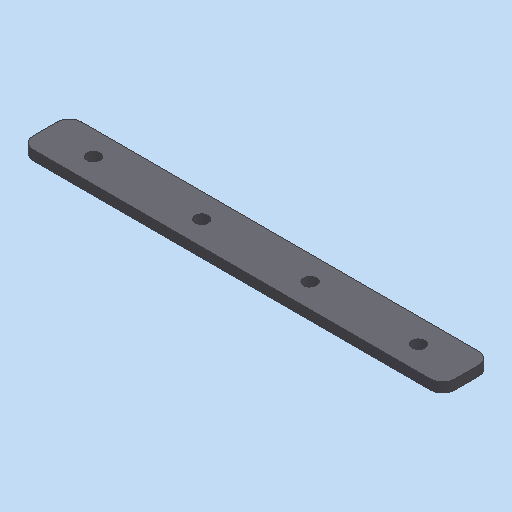
# Autodesk Inventor part: MM0861AN200_G22_145
Saved by Autodesk Inventor 2023.3 (Build 273359000, 359)
## iProperties
Part Number: MM0861AN200_G22_145
Material: 3.1645 AlCu4PbMgMn - AW 2007
Description: =<RBPARTNOTITLE2>
Document SubType Name: Blech
Designer: Benutzer
Mass: 38.572 g
Surface Area: 85.6914 cm^2
Volume: 13.534 cm^3
Density: 2.85 g/cm^3
Sheet Metal Rule: Standard_mm
Appearance: grau AnP
Vendor: ASW
RBCHANGEDESCRIPTION1: Erstfreigabe
RBCHANGENO1: 00
RBDOCUMENTTYPE: DRF
RBDOCUMENTVERSION: 00
RBDRAWINGMAINSCALE: 1:1
RBDRAWINGMISSINGSPEC: --
RBDRAWINGVOLUME: --
RBDSV1: 0850
RBGBDETAILS: 43274
RBGBEDGESIN1: +0,5
RBGBEDGESIN2: +0,2
RBGBEDGESOUT1: -0,3
RBGBEDGESOUT2: -0,1
RBMATERIAL: =<Material>
RBMATMEETS: --
RBMATNO: =<Part Number>
RBORGUNITRESPONSIBLE1: AnP/TEF1
RBPARTMADEOF: 4 x 20 x 175 (FM)
RBPARTNO: SIEHE MNR
RBPARTNOTITLE1: manufactured part
RBPARTNOTITLE2: Anfertigungsteil
RBPARTSAFETYINDICATOR: --
RBSURFACE: anodised grey
RBSURFACE2: eloxiert grau
RBZEDGESNORM: ISO13715:2002-06
RBZGENDIMCLASS: m
RBZGENDIMNORM: ISO 2768-1:1989-11
RBZGENGEOCLASS: H
RBZGENGEONORM: ISO 2768-2:1989-11
RBZSURFACENORM: ISO13D2:2002-02
RBZTOLERANCENORM: ISO 14405-1:2010-12
AnP_Material: =<Material>
AnP_TemplVers: 20190222
AnP_Kategorie: 1
MaxAbmaße: 4 x 20 x 175 (FM)
Author: Benutzer
Keywords: =<RBPARTMADEOF>
Comments: =<RBSURFACE2>
Revision Number: 01
Autodesk Inventor part; units mm, degrees
ref_plane "XZ Plane" through (0, 0, 0) normal (0, 1, 0) x (-1, 0, 0)
sketch "Skizze1" plane through (0, 0, 0) normal (0, 0, 1) x (1, 0, 0)
  line L0 (0, 0) -> (75, 0)
  line L1 (75, 0) -> (75, 20)
  line L2 (75, 20) -> (0, 20)
  line L3 (0, 20) -> (0, 0)
  dimension "d0" = 75
  dimension "d1" = 20
  measures "d0" distance of L2.end L1.end
  measures "d1" distance of L1.end L0.end
extrude "Grobblech1" add sketch "Skizze1" along normal blind 4
sketch "Skizze2" plane through (0, 0, 4) normal (0, 0, 1) x (1, 0, 0)
  line L0 (0, 20) -> (75, 20) projected
  line L1 (0, 0) -> (0, 20) projected
  point P0 (15, 10)
  point P1 (60, 10)
  dimension "d3" = 10
  dimension "d4" = 45
  dimension "d5" = 15
  constraints: 1 horizontal alignment
  measures "d3" distance from line of point (15, 10) L0
  measures "d4" distance of point (60, 10) point (15, 10)
  measures "d5" distance from line of point (15, 10) L1
hole "Bohrung1" at (15, 10, 4) at (60, 10, 4) direction (0, 0, -1) diameter 5.5 depth 4 tip angle 118
sketch "Skizze3" plane through (75, 0, 0) normal (1, 0, 0) x (0, 0, -1)
  line L0 (-4, 20) -> (-4, 0) projected
  line L1 (0, 0) -> (-4, 0) projected
  line L2 (0, 0) -> (0, 20) projected
  line L3 (0, 20) -> (-4, 20) projected
extrude "Extrusion1" add sketch "Skizze3" along normal blind 50
sketch "Skizze4" plane through (0, 0, 0) normal (-1, 0, 0) x (0, 0, 1)
  line L0 (4, 0) -> (4, 20) projected
  line L1 (0, 20) -> (4, 20) projected
  line L2 (0, 20) -> (0, 0) projected
  line L3 (0, 0) -> (4, 0) projected
extrude "Extrusion2" add sketch "Skizze4" along normal blind 50
sketch "Skizze5" plane through (0, 0, 4) normal (0, 0, 1) x (1, 0, 0)
  circle A0 centre (15, 10) radius 2.75 projected
  circle A1 centre (60, 10) radius 2.75 projected
  line L0 (-50, 0) -> (-50, 20) projected
  line L1 (125, 20) -> (125, 0) projected
  point P0 (0, 0)
  point P1 (-30, 10)
  point P2 (105, 10)
  dimension "d18" = 20
  dimension "d19" = 20
  constraints: 2 horizontal alignment
  measures "d18" distance from line of L0 point (-30, 10)
  measures "d19" distance from line of L1 point (105, 10)
hole "Bohrung2" at (-30, 10, 4) at (105, 10, 4) direction (0, 0, -1) diameter 5.5 depth 4 tip angle 118
fillet "Rundung2" radius 5 4 edges at (-50, 0, 2) (125, 0, 2) (125, 20, 2) (-50, 20, 2)
ref_plane "Arbeitsebene1" through (125, 0, 0) normal (1, 0, 0) x (0, 1, 0)
ref_plane "Arbeitsebene2" through (-50, 0, 0) normal (1, 0, 0) x (0, 1, 0)
equation "\"d11\" = Stärke"
equation "\"d25\" = Stärke"
equation "\"d30\" = Stärke"
equation "\"Biegeradius\" = Stärke"
equation "\"BreiteBiegungsfreistellung\" = Stärke"
equation "\"TiefeBiegungsfreistellung\" = 0.5 * Stärke"
equation "\"GrößeEckenfreistellung\" = 4 * Stärke"
equation "\"MinimalRest\" = 2 * Stärke"
equation "\"Übergangsradius\" = Biegeradius"
equation "\"JacobiRadiusGröße\" = Biegeradius"
equation "\"Abstandsgröße\" = Stärke"
equation "\"d2\" = Biegeradius"
equation "\"Stärke\" = 4"
